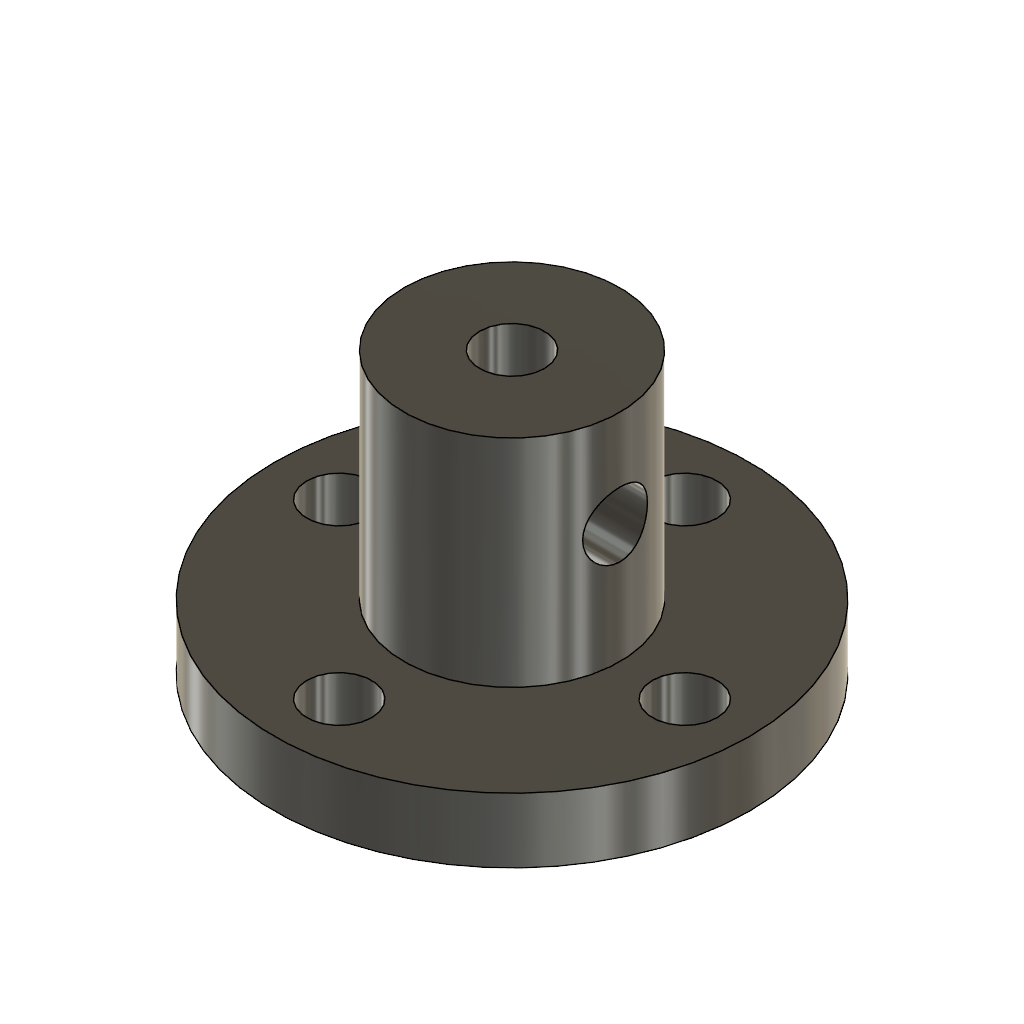
Estructura (Autodesk Fusion 360 archive; units mm, degrees)
design "BRIDA-A-3X22"
Autodesk Fusion 360 part; units mm, degrees
sketch "BRIDA-A-3X22" plane through (0, 0, 0) normal (0, 0, 1) x (1, 0, 0)
  circle A0 centre (0, 0) radius 1.5
  circle A1 centre (0, 0) radius 5
  circle A2 centre (0, 0) radius 11
  line L0 (0, 5) -> (0, 8) construction
  circle A3 centre (0, 8) radius 1.5
  line L1 (0, 0) -> (0, 5) construction
  circle A4 centre (-8, 0) radius 1.5
  circle A5 centre (0, -8) radius 1.5
  circle A6 centre (8, 0) radius 1.5
  point P0 (0, 5)
  dimension "d1" = 3
  dimension "d2" = 10
  dimension "d3" = 22
  dimension "d4" = 3
  dimension "d5" = 3
  dimension "d7" = 360
  constraint coincident A0.centre A1.centre
  constraint concentric A0 A2
  constraint coincident A1 P0
  constraint vertical L0
  constraint coincident L0.end A3.centre
  constraint coincident P0 L0.start
  constraint parallel L0 L1
  measures "d1" diameter of A0
  measures "d2" diameter of A1
  measures "d3" diameter of A2
  measures "d4" distance of P0 L0.end
  measures "d5" diameter of A3
extrude "Extrude1" add sketch "BRIDA-A-3X22" along normal blind 3 contours A1 | A2
extrude "Extrude2" add sketch "BRIDA-A-3X22" along normal blind 10 from surface at 3 contours A1
ref_plane "WorkPlane1" through (5, 0, 8) normal (1, 0, 0) x (0, 0, 1)
sketch "Sketch2" plane through (5, 0, 0) normal (1, 0, 0) x (0, 1, 0)
  line L0 (5, 13) -> (-5, 13)
  line L1 (-5, 3) -> (5, 3)
  line L2 (0, 13) -> (0, 10)
  line L3 (0, 10) -> (0, 8.5)
  circle A0 centre (0, 8.5) radius 1.5
  dimension "d15" = 3
  dimension "d16" = 1.5
  dimension "d17" = 3
  constraint midpoint L0 L2.start
  constraint perpendicular L0 L2
  constraint perpendicular L0 L3
  constraint coincident L3.end A0.centre
  measures "d15" distance of L2.start L2.end
  measures "d16" distance of L2.end L3.end
  measures "d17" diameter of A0
extrude "Extrude3" cut sketch "Sketch2" against normal blind 5
equation "d4 = 6.000 mm / 2"
named bodies: "BRIDA-A-3X22"
